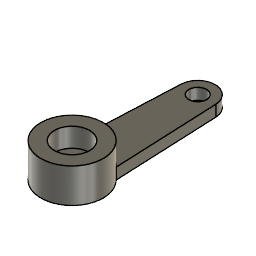
Servo-Motor (Autodesk Fusion 360 archive; units mm, degrees)
design "MicroServo horn"
Autodesk Fusion 360 part; units mm, degrees
sketch "Sketch1" plane through (0, 0, 0) normal (0, 0, 1) x (1, 0, 0)
  circle A0 centre (0, 0) radius 3.5243
  line L0 (-2.4892, 2.4948) -> (-1.9685, 14.2773)
  line L1 (2.4892, 2.4948) -> (1.9685, 14.2773)
  arc A1 (1.9685, 14.2773) -> (-1.9685, 14.2773) centre (0, 14.1903) ccw
  line L2 (-12.7, 16.1608) -> (12.7, 16.1608)
  line L3 (-12.7, -3.5242) -> (12.7, -3.5243)
  circle A2 centre (0, 14.1903) radius 1
  dimension "d1" = 7.0485
  dimension "d2" = 4.9784
  dimension "d5" = 19.685
  dimension "d7" = 3.937
  dimension "d8" = 2
  dimension "d9" = 25.4
  dimension "d10" = 12.7
  constraint coincident A0.centre origin
  constraint coincident A0 L0.start
  constraint coincident A0 L1.start
  constraint tangent L0 A1
  constraint horizontal L2
  constraint tangent A1 L2
  constraint vertical A0.centre A1.centre
  constraint horizontal L0.end L1.end
  constraint tangent A0 L3
  constraint horizontal L3
  constraint horizontal L0.start L1.start
  constraint concentric A1 A2
  constraint vertical L2.start L3.start
  constraint vertical L2.end L3.end
  measures "d1" diameter of A0
  measures "d2" horizontal distance of L0.start L1.start
  measures "d5" distance of L2 L3
  measures "d7" distance of L0.end L1.end
  measures "d8" diameter of A2
  measures "d9" distance of L2.start L2.end
  measures "d10" horizontal distance of A1.centre L2.start
extrude "Extrude1" add sketch "Sketch1" along normal blind 1.27
extrude "Extrude2" add sketch "Sketch1" along normal blind 3.8735 contours A0
sketch "Sketch2" plane through (0, 0, 3.8735) normal (0, 0, 1) x (-1, 0, 0)
  circle A0 centre (0, 0) radius 3.5242
  circle A1 centre (0, 0) radius 1.9812
  dimension "d15" = 3.9624
  constraint coincident A0.centre A1.centre
  measures "d15" diameter of A1
extrude "Extrude3" cut sketch "Sketch2" against normal blind 2.159 contours A1
